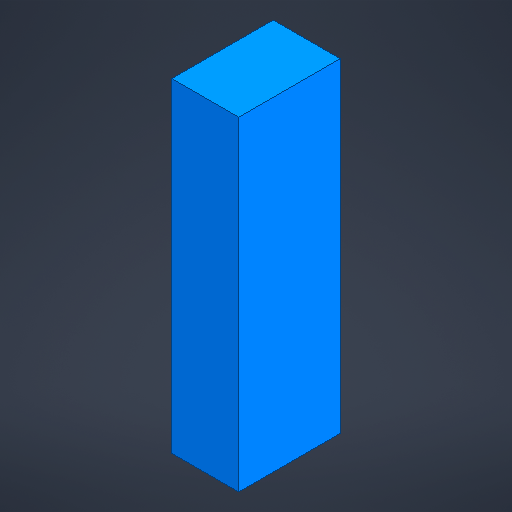
# Autodesk Inventor part: battery_power
Saved by Autodesk Inventor 2026.2 (Build 302298010, 298A)
## iProperties
Created: 2026-10-26
Part Number: battery_power
Material: Générique
Document SubType Name: Modeling
Designer: User
Density: 1 g/cm^3
Appearance: Par défaut
Author: User
Autodesk Inventor part; units mm, degrees
ref_plane "YZ Plane" through (0, 0, 0) normal (1, 0, 0) x (0, 1, 0)
ref_plane "XZ Plane" through (0, 0, 0) normal (0, 1, 0) x (-1, 0, 0)
ref_plane "XY Plane" through (0, 0, 0) normal (0, 0, 1) x (1, 0, 0)
sketch "Esquisse1" plane through (0, 0, 0) normal (0, 1, 0) x (-1, 0, 0)
  line L0 (16.5, 25) -> (-16.5, 25)
  line L1 (-16.5, 25) -> (-16.5, -25)
  line L2 (-16.5, -25) -> (16.5, -25)
  line L3 (16.5, -25) -> (16.5, 25)
  point P0 (0, 0)
  dimension "d0" = 50
  dimension "d1" = 33
  dimension "d2" = 25
  dimension "d3" = 16.5
  constraints: 8 end point, 2 parallel, 1 horizontal, 1 perpendicular
  measures "d0" distance of L2.end L0.start
  measures "d1" distance of L1.end L2.end
  measures "d2" distance from line of L2 point (0, 0)
  measures "d3" distance from line of point (0, 0) L1
extrude "Extrusion1" add sketch "Esquisse1" along normal blind 160
equation "\"d2\" = 0.5 * d0"
equation "\"d3\" = 0.5 * d1"
